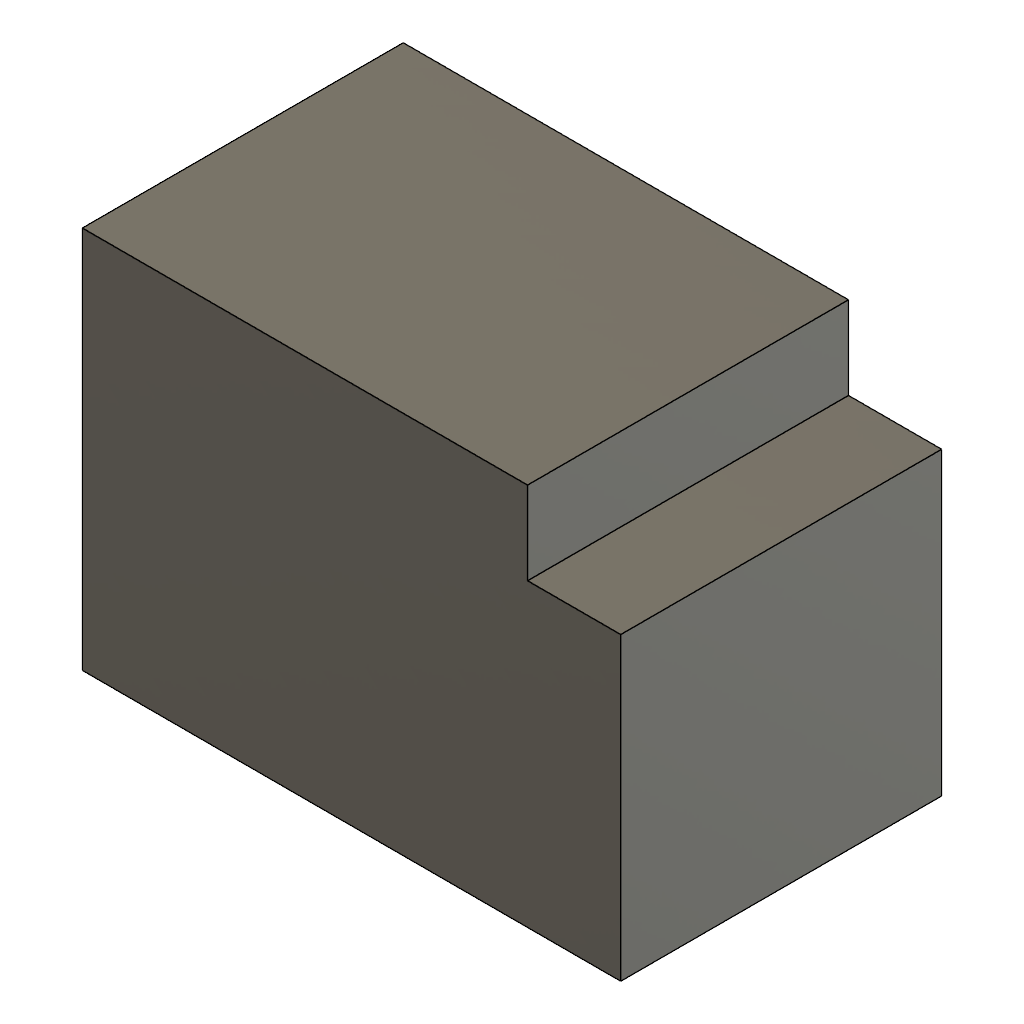
CornerHeldOut (Autodesk Fusion 360 design; units mm, degrees)
part number: 2026-11-22-11-52-09-815
Autodesk Fusion 360 part; units mm, degrees
sketch "Base sketch" plane through (0, 0, 0) normal (0, 0, 1) x (1, 0, 0)
  line L0 (-20, -10) -> (32, -10)
  line L1 (32, -10) -> (32, 27)
  line L2 (32, 27) -> (-20, 27)
  line L3 (-20, 27) -> (-20, -10)
extrude "Base" add sketch "Base sketch" along normal blind 31
sketch "Corner sketch" plane through (0, 0, 0) normal (0, 0, 1) x (1, 0, 0)
  line L0 (23, 19) -> (40, 19)
  line L1 (40, 19) -> (40, 40)
  line L2 (40, 40) -> (23, 40)
  line L3 (23, 40) -> (23, 19)
extrude "Corner" cut sketch "Corner sketch" along normal blind 31
